00_posture_strip_first_concept (Autodesk Fusion 360 design; units mm, degrees)
part number: 2026-10-12-18-56-29-942
Autodesk Fusion 360 part; units mm, degrees
sketch "Pad L" plane through (0, 0, 0) normal (0, 0, 1) x (1, 0, 0)
  ellipse E0 centre (-70, 0) end of major axis (-47.5, 0) minor radius 17.5
  line L0 (-92.5, 0) -> (-47.5, 0) construction
  line L1 (-70, 17.5) -> (-70, -17.5) construction
  constraint coincident E0 L0.start
  constraint coincident E0 L0.end
  constraint coincident E0 L1.start
  constraint coincident E0 L1.end
extrude "Extrude1" add sketch "Pad L" along normal blind 0.8 from surface at -0.8 makes body 1
sketch "Pad R" plane through (0, 0, 0) normal (0, 0, 1) x (1, 0, 0)
  ellipse E0 centre (70, 0) end of major axis (92.5, 0) minor radius 17.5
  line L0 (47.5, 0) -> (92.5, 0) construction
  line L1 (70, 17.5) -> (70, -17.5) construction
  constraint coincident E0 L0.start
  constraint coincident E0 L0.end
  constraint coincident E0 L1.start
  constraint coincident E0 L1.end
extrude "Extrude2" add sketch "Pad R" along normal blind 0.8 from surface at -0.8 separate body makes body 2
sketch "Strip" plane through (0, 0, 0) normal (0, 0, 1) x (1, 0, 0)
  line L0 (-76, -10) -> (76, -10)
  arc A0 (76, -10) -> (85, -1) centre (76, -1) ccw
  line L1 (85, -1) -> (85, 1)
  arc A1 (85, 1) -> (76, 10) centre (76, 1) ccw
  line L2 (76, 10) -> (-76, 10)
  arc A2 (-76, 10) -> (-85, 1) centre (-76, 1) ccw
  line L3 (-85, 1) -> (-85, -1)
  arc A3 (-85, -1) -> (-76, -10) centre (-76, -1) ccw
extrude "Extrude3" add sketch "Strip" along normal blind 1 separate body makes body 3
sketch "Tether Channel" plane through (0, 0, 0) normal (0, 0, 1) x (1, 0, 0)
  line L0 (-52.6, -1.5) -> (78.6, -1.5)
  arc A0 (78.6, -1.5) -> (80, -0.1) centre (78.6, -0.1) ccw
  line L1 (80, -0.1) -> (80, 0.1)
  arc A1 (80, 0.1) -> (78.6, 1.5) centre (78.6, 0.1) ccw
  line L2 (78.6, 1.5) -> (-52.6, 1.5)
  arc A2 (-52.6, 1.5) -> (-54, 0.1) centre (-52.6, 0.1) ccw
  line L3 (-54, 0.1) -> (-54, -0.1)
  arc A3 (-54, -0.1) -> (-52.6, -1.5) centre (-52.6, -0.1) ccw
extrude "Extrude4" add sketch "Tether Channel" along normal blind 0.6 from surface at 1 bodies 3
sketch "Pod" plane through (0, 0, 0) normal (0, 0, 1) x (1, 0, 0)
  line L0 (-80, -13) -> (-60, -13)
  arc A0 (-60, -13) -> (-54, -7) centre (-60, -7) ccw
  line L1 (-54, -7) -> (-54, 7)
  arc A1 (-54, 7) -> (-60, 13) centre (-60, 7) ccw
  line L2 (-60, 13) -> (-80, 13)
  arc A2 (-80, 13) -> (-86, 7) centre (-80, 7) ccw
  line L3 (-86, 7) -> (-86, -7)
  arc A3 (-86, -7) -> (-80, -13) centre (-80, -7) ccw
extrude "Extrude5" add sketch "Pod" along normal blind 6 from surface at 1 separate body makes body 4
fillet "Fillet1" radius 2 64 edges at (-84.2426, -11.2426, 7) (-70, -13, 7) (-55.7574, -11.2426, 7) (-54, 0, 7) (-55.7574, 11.2426, 7) (-70, 13, 7) (-84.2426, 11.2426, 7) (-86, 0, 7) (-70, -13, 7) (-55.7574, -11.2426, 7) (-54, 0, 7) (-55.7574, 11.2426, 7) (-70, 13, 7) (-84.2426, 11.2426, 7) (-86, 0, 7) (-84.2426, -11.2426, 7) (-55.7574, -11.2426, 7) (-54, 0, 7) (-55.7574, 11.2426, 7) (-70, 13, 7) (-84.2426, 11.2426, 7) (-86, 0, 7) (-84.2426, -11.2426, 7) (-70, -13, 7) (-54, 0, 7) (-55.7574, 11.2426, 7) (-70, 13, 7) (-84.2426, 11.2426, 7) (-86, 0, 7) (-84.2426, -11.2426, 7) (-70, -13, 7) (-55.7574, -11.2426, 7) (-55.7574, 11.2426, 7) (-70, 13, 7) (-84.2426, 11.2426, 7) (-86, 0, 7) (-84.2426, -11.2426, 7) (-70, -13, 7) (-55.7574, -11.2426, 7) (-54, 0, 7) (-70, 13, 7) (-84.2426, 11.2426, 7) (-86, 0, 7) (-84.2426, -11.2426, 7) (-70, -13, 7) (-55.7574, -11.2426, 7) (-54, 0, 7) (-55.7574, 11.2426, 7) (-84.2426, 11.2426, 7) (-86, 0, 7) (-84.2426, -11.2426, 7) (-70, -13, 7) (-55.7574, -11.2426, 7) (-54, 0, 7) (-55.7574, 11.2426, 7) (-70, 13, 7) (-86, 0, 7) (-84.2426, -11.2426, 7) (-70, -13, 7) (-55.7574, -11.2426, 7) (-54, 0, 7) (-55.7574, 11.2426, 7) (-70, 13, 7) (-84.2426, 11.2426, 7) on bodies 4
sketch "Slider Slot" plane through (0, 0, 0) normal (0, 0, 1) x (1, 0, 0)
  line L0 (-75.6, 4.5) -> (-64.4, 4.5)
  arc A0 (-64.4, 4.5) -> (-63, 5.9) centre (-64.4, 5.9) ccw
  line L1 (-63, 5.9) -> (-63, 6.1)
  arc A1 (-63, 6.1) -> (-64.4, 7.5) centre (-64.4, 6.1) ccw
  line L2 (-64.4, 7.5) -> (-75.6, 7.5)
  arc A2 (-75.6, 7.5) -> (-77, 6.1) centre (-75.6, 6.1) ccw
  line L3 (-77, 6.1) -> (-77, 5.9)
  arc A3 (-77, 5.9) -> (-75.6, 4.5) centre (-75.6, 5.9) ccw
extrude "Extrude6" cut sketch "Slider Slot" along normal blind 0.6 from surface at 6.5 bodies 4
sketch "Slider Knob" plane through (0, 0, 0) normal (0, 0, 1) x (1, 0, 0)
  line L0 (-73.8, 4.9) -> (-72.2, 4.9)
  arc A0 (-72.2, 4.9) -> (-71.2, 5.9) centre (-72.2, 5.9) ccw
  line L1 (-71.2, 5.9) -> (-71.2, 6.1)
  arc A1 (-71.2, 6.1) -> (-72.2, 7.1) centre (-72.2, 6.1) ccw
  line L2 (-72.2, 7.1) -> (-73.8, 7.1)
  arc A2 (-73.8, 7.1) -> (-74.8, 6.1) centre (-73.8, 6.1) ccw
  line L3 (-74.8, 6.1) -> (-74.8, 5.9)
  arc A3 (-74.8, 5.9) -> (-73.8, 4.9) centre (-73.8, 5.9) ccw
extrude "Extrude7" add sketch "Slider Knob" along normal blind 0.9 from surface at 6.5 separate body makes body 5
named bodies: "Adhesive Pad L", "Adhesive Pad R", "Flex Strip", "Electronics Pod", "Threshold Slider"
